Autodesk Fusion 360 part; units mm, degrees
(part 3 of 5)
sketch "Receiving deck roller sketch (8)" plane through (0, -195, 0) normal (0, 1, 0) x (1, 0, 0) in component "MM25 Y carriage and powered receiving deck"
  circle A0 centre (-416, 136) radius 8
extrude "Receiving deck roller (8)" add sketch "Receiving deck roller sketch (8)" along normal blind 390 separate body makes body 155 in component "MM25 Y carriage and powered receiving deck"
ref_plane "WorkPlane17" through (0, -195, 0) normal (0, 1, 0) x (0, 0, 1) in component "MM25 Y carriage and powered receiving deck"
sketch "Receiving deck roller sketch (9)" plane through (0, -195, 0) normal (0, 1, 0) x (1, 0, 0) in component "MM25 Y carriage and powered receiving deck"
  circle A0 centre (-368, 136) radius 8
extrude "Receiving deck roller (9)" add sketch "Receiving deck roller sketch (9)" along normal blind 390 separate body makes body 156 in component "MM25 Y carriage and powered receiving deck"
ref_plane "WorkPlane18" through (0, -195, 0) normal (0, 1, 0) x (0, 0, 1) in component "MM25 Y carriage and powered receiving deck"
sketch "Receiving deck roller sketch (10)" plane through (0, -195, 0) normal (0, 1, 0) x (1, 0, 0) in component "MM25 Y carriage and powered receiving deck"
  circle A0 centre (-320, 136) radius 8
extrude "Receiving deck roller (10)" add sketch "Receiving deck roller sketch (10)" along normal blind 390 separate body makes body 157 in component "MM25 Y carriage and powered receiving deck"
ref_plane "WorkPlane1" through (0, 0, -132) normal (0, 0, 1) x (1, 0, 0) in component "MM26 Folding receiving bridge"
sketch "Thin supported intake bridge sketch" plane through (0, 0, -132) normal (0, 0, 1) x (1, 0, 0) in component "MM26 Folding receiving bridge"
  line L0 (-310, -190) -> (-255, -190)
  line L1 (-255, -190) -> (-255, 190)
  line L2 (-255, 190) -> (-310, 190)
  line L3 (-310, 190) -> (-310, -190)
extrude "Thin supported intake bridge" add sketch "Thin supported intake bridge sketch" along normal blind 4 separate body makes body 158 in component "MM26 Folding receiving bridge"
sketch "Sketch11" plane through (0, 0, 0) normal (0, 0, 1) x (1, 0, 0) in component "MM01 Pressure shell and neck"
sketch "Sketch4" plane through (0, 0, 0) normal (0, 0, 1) x (1, 0, 0) in component "MM24 Elevator Z crossbeam"
sketch "Sketch19" plane through (0, 0, 0) normal (0, 0, 1) x (1, 0, 0) in component "MM25 Y carriage and powered receiving deck"
  point P0 (-310, 0)
ref_plane "WorkPlane1" through (0, 0, -255) normal (0, 0, 1) x (1, 0, 0) in component "MM40 Receiver fixed guide beams"
sketch "Fixed guide box beam sketch" plane through (0, 0, -255) normal (0, 0, 1) x (1, 0, 0) in component "MM40 Receiver fixed guide beams"
  line L0 (-3300, -190) -> (-1660, -190)
  line L1 (-1660, -190) -> (-1660, -160)
  line L2 (-1660, -160) -> (-3300, -160)
  line L3 (-3300, -160) -> (-3300, -190)
extrude "Fixed guide box beam" add sketch "Fixed guide box beam sketch" along normal blind 50 separate body makes body 159 in component "MM40 Receiver fixed guide beams"
ref_plane "WorkPlane2" through (0, 0, -252) normal (0, 0, 1) x (1, 0, 0) in component "MM40 Receiver fixed guide beams"
sketch "Guide beam hollow section sketch" plane through (0, 0, -252) normal (0, 0, 1) x (1, 0, 0) in component "MM40 Receiver fixed guide beams"
  line L0 (-3301, -187) -> (-1659, -187)
  line L1 (-1659, -187) -> (-1659, -163)
  line L2 (-1659, -163) -> (-3301, -163)
  line L3 (-3301, -163) -> (-3301, -187)
extrude "Guide beam hollow section" cut sketch "Guide beam hollow section sketch" along normal blind 44 bodies 159 in component "MM40 Receiver fixed guide beams"
ref_plane "WorkPlane3" through (0, 0, -255) normal (0, 0, 1) x (1, 0, 0) in component "MM40 Receiver fixed guide beams"
sketch "Fixed guide box beam sketch (1)" plane through (0, 0, -255) normal (0, 0, 1) x (1, 0, 0) in component "MM40 Receiver fixed guide beams"
  line L0 (-3300, 160) -> (-1660, 160)
  line L1 (-1660, 160) -> (-1660, 190)
  line L2 (-1660, 190) -> (-3300, 190)
  line L3 (-3300, 190) -> (-3300, 160)
extrude "Fixed guide box beam (1)" add sketch "Fixed guide box beam sketch (1)" along normal blind 50 separate body makes body 160 in component "MM40 Receiver fixed guide beams"
ref_plane "WorkPlane4" through (0, 0, -252) normal (0, 0, 1) x (1, 0, 0) in component "MM40 Receiver fixed guide beams"
sketch "Guide beam hollow section sketch (1)" plane through (0, 0, -252) normal (0, 0, 1) x (1, 0, 0) in component "MM40 Receiver fixed guide beams"
  line L0 (-3301, 163) -> (-1659, 163)
  line L1 (-1659, 163) -> (-1659, 187)
  line L2 (-1659, 187) -> (-3301, 187)
  line L3 (-3301, 187) -> (-3301, 163)
extrude "Guide beam hollow section (1)" cut sketch "Guide beam hollow section sketch (1)" along normal blind 44 bodies 159 160 in component "MM40 Receiver fixed guide beams"
ref_plane "WorkPlane1" through (0, 0, -650) normal (0, 0, 1) x (1, 0, 0) in component "MM41 Receiver mounting stand"
sketch "Bolted mounting foot sketch" plane through (0, 0, -650) normal (0, 0, 1) x (1, 0, 0) in component "MM41 Receiver mounting stand"
  line L0 (-3250, -225) -> (-3150, -225)
  line L1 (-3150, -225) -> (-3150, -125)
  line L2 (-3150, -125) -> (-3250, -125)
  line L3 (-3250, -125) -> (-3250, -225)
extrude "Bolted mounting foot" add sketch "Bolted mounting foot sketch" along normal blind 20 separate body makes body 161 in component "MM41 Receiver mounting stand"
ref_plane "WorkPlane2" through (0, 0, -630) normal (0, 0, 1) x (1, 0, 0) in component "MM41 Receiver mounting stand"
sketch "Vertical support post sketch" plane through (0, 0, -630) normal (0, 0, 1) x (1, 0, 0) in component "MM41 Receiver mounting stand"
  line L0 (-3230, -205) -> (-3170, -205)
  line L1 (-3170, -205) -> (-3170, -145)
  line L2 (-3170, -145) -> (-3230, -145)
  line L3 (-3230, -145) -> (-3230, -205)
extrude "Vertical support post" add sketch "Vertical support post sketch" along normal blind 315 separate body makes body 162 in component "MM41 Receiver mounting stand"
ref_plane "WorkPlane3" through (0, 0, -631) normal (0, 0, 1) x (1, 0, 0) in component "MM41 Receiver mounting stand"
sketch "Post hollow section sketch" plane through (0, 0, -631) normal (0, 0, 1) x (1, 0, 0) in component "MM41 Receiver mounting stand"
  line L0 (-3224, -199) -> (-3176, -199)
  line L1 (-3176, -199) -> (-3176, -151)
  line L2 (-3176, -151) -> (-3224, -151)
  line L3 (-3224, -151) -> (-3224, -199)
extrude "Post hollow section" cut sketch "Post hollow section sketch" along normal blind 377 bodies 161 162 in component "MM41 Receiver mounting stand"
ref_plane "WorkPlane4" through (0, 0, -655) normal (0, 0, 1) x (1, 0, 0) in component "MM41 Receiver mounting stand"
sketch "M8 mounting clearance sketch" plane through (0, 0, -655) normal (0, 0, 1) x (1, 0, 0) in component "MM41 Receiver mounting stand"
  circle A0 centre (-3238, -213) radius 4.25
extrude "M8 mounting clearance" cut sketch "M8 mounting clearance sketch" along normal blind 30 bodies 161 162 in component "MM41 Receiver mounting stand"
ref_plane "WorkPlane5" through (0, 0, -655) normal (0, 0, 1) x (1, 0, 0) in component "MM41 Receiver mounting stand"
sketch "M8 mounting clearance sketch (1)" plane through (0, 0, -655) normal (0, 0, 1) x (1, 0, 0) in component "MM41 Receiver mounting stand"
  circle A0 centre (-3238, -137) radius 4.25
extrude "M8 mounting clearance (1)" cut sketch "M8 mounting clearance sketch (1)" along normal blind 30 bodies 161 162 in component "MM41 Receiver mounting stand"
ref_plane "WorkPlane6" through (0, 0, -655) normal (0, 0, 1) x (1, 0, 0) in component "MM41 Receiver mounting stand"
sketch "M8 mounting clearance sketch (2)" plane through (0, 0, -655) normal (0, 0, 1) x (1, 0, 0) in component "MM41 Receiver mounting stand"
  circle A0 centre (-3162, -213) radius 4.25
extrude "M8 mounting clearance (2)" cut sketch "M8 mounting clearance sketch (2)" along normal blind 30 bodies 161 162 in component "MM41 Receiver mounting stand"
ref_plane "WorkPlane7" through (0, 0, -655) normal (0, 0, 1) x (1, 0, 0) in component "MM41 Receiver mounting stand"
sketch "M8 mounting clearance sketch (3)" plane through (0, 0, -655) normal (0, 0, 1) x (1, 0, 0) in component "MM41 Receiver mounting stand"
  circle A0 centre (-3162, -137) radius 4.25
extrude "M8 mounting clearance (3)" cut sketch "M8 mounting clearance sketch (3)" along normal blind 30 bodies 161 162 in component "MM41 Receiver mounting stand"
ref_plane "WorkPlane8" through (0, 0, -650) normal (0, 0, 1) x (1, 0, 0) in component "MM41 Receiver mounting stand"
sketch "Bolted mounting foot sketch (1)" plane through (0, 0, -650) normal (0, 0, 1) x (1, 0, 0) in component "MM41 Receiver mounting stand"
  line L0 (-3250, 125) -> (-3150, 125)
  line L1 (-3150, 125) -> (-3150, 225)
  line L2 (-3150, 225) -> (-3250, 225)
  line L3 (-3250, 225) -> (-3250, 125)
extrude "Bolted mounting foot (1)" add sketch "Bolted mounting foot sketch (1)" along normal blind 20 separate body makes body 163 in component "MM41 Receiver mounting stand"
ref_plane "WorkPlane9" through (0, 0, -630) normal (0, 0, 1) x (1, 0, 0) in component "MM41 Receiver mounting stand"
sketch "Vertical support post sketch (1)" plane through (0, 0, -630) normal (0, 0, 1) x (1, 0, 0) in component "MM41 Receiver mounting stand"
  line L0 (-3230, 145) -> (-3170, 145)
  line L1 (-3170, 145) -> (-3170, 205)
  line L2 (-3170, 205) -> (-3230, 205)
  line L3 (-3230, 205) -> (-3230, 145)
extrude "Vertical support post (1)" add sketch "Vertical support post sketch (1)" along normal blind 315 separate body makes body 164 in component "MM41 Receiver mounting stand"
ref_plane "WorkPlane10" through (0, 0, -631) normal (0, 0, 1) x (1, 0, 0) in component "MM41 Receiver mounting stand"
sketch "Post hollow section sketch (1)" plane through (0, 0, -631) normal (0, 0, 1) x (1, 0, 0) in component "MM41 Receiver mounting stand"
  line L0 (-3224, 151) -> (-3176, 151)
  line L1 (-3176, 151) -> (-3176, 199)
  line L2 (-3176, 199) -> (-3224, 199)
  line L3 (-3224, 199) -> (-3224, 151)
extrude "Post hollow section (1)" cut sketch "Post hollow section sketch (1)" along normal blind 377 bodies 161 162 163 164 in component "MM41 Receiver mounting stand"
ref_plane "WorkPlane11" through (0, 0, -655) normal (0, 0, 1) x (1, 0, 0) in component "MM41 Receiver mounting stand"
sketch "M8 mounting clearance sketch (4)" plane through (0, 0, -655) normal (0, 0, 1) x (1, 0, 0) in component "MM41 Receiver mounting stand"
  circle A0 centre (-3238, 137) radius 4.25
extrude "M8 mounting clearance (4)" cut sketch "M8 mounting clearance sketch (4)" along normal blind 30 bodies 161 162 163 164 in component "MM41 Receiver mounting stand"
ref_plane "WorkPlane12" through (0, 0, -655) normal (0, 0, 1) x (1, 0, 0) in component "MM41 Receiver mounting stand"
sketch "M8 mounting clearance sketch (5)" plane through (0, 0, -655) normal (0, 0, 1) x (1, 0, 0) in component "MM41 Receiver mounting stand"
  circle A0 centre (-3238, 213) radius 4.25
extrude "M8 mounting clearance (5)" cut sketch "M8 mounting clearance sketch (5)" along normal blind 30 bodies 161 162 163 164 in component "MM41 Receiver mounting stand"
ref_plane "WorkPlane13" through (0, 0, -655) normal (0, 0, 1) x (1, 0, 0) in component "MM41 Receiver mounting stand"
sketch "M8 mounting clearance sketch (6)" plane through (0, 0, -655) normal (0, 0, 1) x (1, 0, 0) in component "MM41 Receiver mounting stand"
  circle A0 centre (-3162, 137) radius 4.25
extrude "M8 mounting clearance (6)" cut sketch "M8 mounting clearance sketch (6)" along normal blind 30 bodies 161 162 163 164 in component "MM41 Receiver mounting stand"
ref_plane "WorkPlane14" through (0, 0, -655) normal (0, 0, 1) x (1, 0, 0) in component "MM41 Receiver mounting stand"
sketch "M8 mounting clearance sketch (7)" plane through (0, 0, -655) normal (0, 0, 1) x (1, 0, 0) in component "MM41 Receiver mounting stand"
  circle A0 centre (-3162, 213) radius 4.25
extrude "M8 mounting clearance (7)" cut sketch "M8 mounting clearance sketch (7)" along normal blind 30 bodies 161 162 163 164 in component "MM41 Receiver mounting stand"
ref_plane "WorkPlane15" through (0, 0, -650) normal (0, 0, 1) x (1, 0, 0) in component "MM41 Receiver mounting stand"
sketch "Bolted mounting foot sketch (2)" plane through (0, 0, -650) normal (0, 0, 1) x (1, 0, 0) in component "MM41 Receiver mounting stand"
  line L0 (-2450, -225) -> (-2350, -225)
  line L1 (-2350, -225) -> (-2350, -125)
  line L2 (-2350, -125) -> (-2450, -125)
  line L3 (-2450, -125) -> (-2450, -225)
extrude "Bolted mounting foot (2)" add sketch "Bolted mounting foot sketch (2)" along normal blind 20 separate body makes body 165 in component "MM41 Receiver mounting stand"
ref_plane "WorkPlane16" through (0, 0, -630) normal (0, 0, 1) x (1, 0, 0) in component "MM41 Receiver mounting stand"
sketch "Vertical support post sketch (2)" plane through (0, 0, -630) normal (0, 0, 1) x (1, 0, 0) in component "MM41 Receiver mounting stand"
  line L0 (-2430, -205) -> (-2370, -205)
  line L1 (-2370, -205) -> (-2370, -145)
  line L2 (-2370, -145) -> (-2430, -145)
  line L3 (-2430, -145) -> (-2430, -205)
extrude "Vertical support post (2)" add sketch "Vertical support post sketch (2)" along normal blind 315 separate body makes body 166 in component "MM41 Receiver mounting stand"
ref_plane "WorkPlane17" through (0, 0, -631) normal (0, 0, 1) x (1, 0, 0) in component "MM41 Receiver mounting stand"
sketch "Post hollow section sketch (2)" plane through (0, 0, -631) normal (0, 0, 1) x (1, 0, 0) in component "MM41 Receiver mounting stand"
  line L0 (-2424, -199) -> (-2376, -199)
  line L1 (-2376, -199) -> (-2376, -151)
  line L2 (-2376, -151) -> (-2424, -151)
  line L3 (-2424, -151) -> (-2424, -199)
extrude "Post hollow section (2)" cut sketch "Post hollow section sketch (2)" along normal blind 377 bodies 161 162 163 164 165 166 in component "MM41 Receiver mounting stand"
ref_plane "WorkPlane18" through (0, 0, -655) normal (0, 0, 1) x (1, 0, 0) in component "MM41 Receiver mounting stand"
sketch "M8 mounting clearance sketch (8)" plane through (0, 0, -655) normal (0, 0, 1) x (1, 0, 0) in component "MM41 Receiver mounting stand"
  circle A0 centre (-2438, -213) radius 4.25
extrude "M8 mounting clearance (8)" cut sketch "M8 mounting clearance sketch (8)" along normal blind 30 bodies 161 162 163 164 165 166 in component "MM41 Receiver mounting stand"
ref_plane "WorkPlane19" through (0, 0, -655) normal (0, 0, 1) x (1, 0, 0) in component "MM41 Receiver mounting stand"
sketch "M8 mounting clearance sketch (9)" plane through (0, 0, -655) normal (0, 0, 1) x (1, 0, 0) in component "MM41 Receiver mounting stand"
  circle A0 centre (-2438, -137) radius 4.25
extrude "M8 mounting clearance (9)" cut sketch "M8 mounting clearance sketch (9)" along normal blind 30 bodies 161 162 163 164 165 166 in component "MM41 Receiver mounting stand"
ref_plane "WorkPlane20" through (0, 0, -655) normal (0, 0, 1) x (1, 0, 0) in component "MM41 Receiver mounting stand"
sketch "M8 mounting clearance sketch (10)" plane through (0, 0, -655) normal (0, 0, 1) x (1, 0, 0) in component "MM41 Receiver mounting stand"
  circle A0 centre (-2362, -213) radius 4.25
extrude "M8 mounting clearance (10)" cut sketch "M8 mounting clearance sketch (10)" along normal blind 30 bodies 161 162 163 164 165 166 in component "MM41 Receiver mounting stand"
ref_plane "WorkPlane21" through (0, 0, -655) normal (0, 0, 1) x (1, 0, 0) in component "MM41 Receiver mounting stand"
sketch "M8 mounting clearance sketch (11)" plane through (0, 0, -655) normal (0, 0, 1) x (1, 0, 0) in component "MM41 Receiver mounting stand"
  circle A0 centre (-2362, -137) radius 4.25
extrude "M8 mounting clearance (11)" cut sketch "M8 mounting clearance sketch (11)" along normal blind 30 bodies 161 162 163 164 165 166 in component "MM41 Receiver mounting stand"
ref_plane "WorkPlane22" through (0, 0, -650) normal (0, 0, 1) x (1, 0, 0) in component "MM41 Receiver mounting stand"
sketch "Bolted mounting foot sketch (3)" plane through (0, 0, -650) normal (0, 0, 1) x (1, 0, 0) in component "MM41 Receiver mounting stand"
  line L0 (-2450, 125) -> (-2350, 125)
  line L1 (-2350, 125) -> (-2350, 225)
  line L2 (-2350, 225) -> (-2450, 225)
  line L3 (-2450, 225) -> (-2450, 125)
extrude "Bolted mounting foot (3)" add sketch "Bolted mounting foot sketch (3)" along normal blind 20 separate body makes body 167 in component "MM41 Receiver mounting stand"
ref_plane "WorkPlane23" through (0, 0, -630) normal (0, 0, 1) x (1, 0, 0) in component "MM41 Receiver mounting stand"
sketch "Vertical support post sketch (3)" plane through (0, 0, -630) normal (0, 0, 1) x (1, 0, 0) in component "MM41 Receiver mounting stand"
  line L0 (-2430, 145) -> (-2370, 145)
  line L1 (-2370, 145) -> (-2370, 205)
  line L2 (-2370, 205) -> (-2430, 205)
  line L3 (-2430, 205) -> (-2430, 145)
extrude "Vertical support post (3)" add sketch "Vertical support post sketch (3)" along normal blind 315 separate body makes body 168 in component "MM41 Receiver mounting stand"
ref_plane "WorkPlane24" through (0, 0, -631) normal (0, 0, 1) x (1, 0, 0) in component "MM41 Receiver mounting stand"
sketch "Post hollow section sketch (3)" plane through (0, 0, -631) normal (0, 0, 1) x (1, 0, 0) in component "MM41 Receiver mounting stand"
  line L0 (-2424, 151) -> (-2376, 151)
  line L1 (-2376, 151) -> (-2376, 199)
  line L2 (-2376, 199) -> (-2424, 199)
  line L3 (-2424, 199) -> (-2424, 151)
extrude "Post hollow section (3)" cut sketch "Post hollow section sketch (3)" along normal blind 377 bodies 161 162 163 164 165 166 167 168 in component "MM41 Receiver mounting stand"
ref_plane "WorkPlane25" through (0, 0, -655) normal (0, 0, 1) x (1, 0, 0) in component "MM41 Receiver mounting stand"
sketch "M8 mounting clearance sketch (12)" plane through (0, 0, -655) normal (0, 0, 1) x (1, 0, 0) in component "MM41 Receiver mounting stand"
  circle A0 centre (-2438, 137) radius 4.25
extrude "M8 mounting clearance (12)" cut sketch "M8 mounting clearance sketch (12)" along normal blind 30 bodies 161 162 163 164 165 166 167 168 in component "MM41 Receiver mounting stand"
ref_plane "WorkPlane26" through (0, 0, -655) normal (0, 0, 1) x (1, 0, 0) in component "MM41 Receiver mounting stand"
sketch "M8 mounting clearance sketch (13)" plane through (0, 0, -655) normal (0, 0, 1) x (1, 0, 0) in component "MM41 Receiver mounting stand"
  circle A0 centre (-2438, 213) radius 4.25
extrude "M8 mounting clearance (13)" cut sketch "M8 mounting clearance sketch (13)" along normal blind 30 bodies 161 162 163 164 165 166 167 168 in component "MM41 Receiver mounting stand"
ref_plane "WorkPlane27" through (0, 0, -655) normal (0, 0, 1) x (1, 0, 0) in component "MM41 Receiver mounting stand"
sketch "M8 mounting clearance sketch (14)" plane through (0, 0, -655) normal (0, 0, 1) x (1, 0, 0) in component "MM41 Receiver mounting stand"
  circle A0 centre (-2362, 137) radius 4.25
extrude "M8 mounting clearance (14)" cut sketch "M8 mounting clearance sketch (14)" along normal blind 30 bodies 161 162 163 164 165 166 167 168 in component "MM41 Receiver mounting stand"
ref_plane "WorkPlane28" through (0, 0, -655) normal (0, 0, 1) x (1, 0, 0) in component "MM41 Receiver mounting stand"
sketch "M8 mounting clearance sketch (15)" plane through (0, 0, -655) normal (0, 0, 1) x (1, 0, 0) in component "MM41 Receiver mounting stand"
  circle A0 centre (-2362, 213) radius 4.25
extrude "M8 mounting clearance (15)" cut sketch "M8 mounting clearance sketch (15)" along normal blind 30 bodies 161 162 163 164 165 166 167 168 in component "MM41 Receiver mounting stand"
ref_plane "WorkPlane1" through (0, 0, -680) normal (0, 0, 1) x (1, 0, 0) in component "REF Existing receiver structural deck ASSUMED"
sketch "Assumed receiver structural deck sketch" plane through (0, 0, -680) normal (0, 0, 1) x (1, 0, 0) in component "REF Existing receiver structural deck ASSUMED"
  line L0 (-3400, -475) -> (-2300, -475)
  line L1 (-2300, -475) -> (-2300, 475)
  line L2 (-2300, 475) -> (-3400, 475)
  line L3 (-3400, 475) -> (-3400, -475)
extrude "Assumed receiver structural deck" add sketch "Assumed receiver structural deck sketch" along normal blind 30 separate body makes body 169 in component "REF Existing receiver structural deck ASSUMED"
ref_plane "WorkPlane2" through (0, 0, -685) normal (0, 0, 1) x (1, 0, 0) in component "REF Existing receiver structural deck ASSUMED"
sketch "Reference deck bolt clearance sketch" plane through (0, 0, -685) normal (0, 0, 1) x (1, 0, 0) in component "REF Existing receiver structural deck ASSUMED"
  circle A0 centre (-3238, -213) radius 4.25
extrude "Reference deck bolt clearance" cut sketch "Reference deck bolt clearance sketch" along normal blind 40 bodies 169 in component "REF Existing receiver structural deck ASSUMED"
ref_plane "WorkPlane3" through (0, 0, -685) normal (0, 0, 1) x (1, 0, 0) in component "REF Existing receiver structural deck ASSUMED"
sketch "Reference deck bolt clearance sketch (1)" plane through (0, 0, -685) normal (0, 0, 1) x (1, 0, 0) in component "REF Existing receiver structural deck ASSUMED"
  circle A0 centre (-3238, -137) radius 4.25
extrude "Reference deck bolt clearance (1)" cut sketch "Reference deck bolt clearance sketch (1)" along normal blind 40 bodies 169 in component "REF Existing receiver structural deck ASSUMED"
ref_plane "WorkPlane4" through (0, 0, -685) normal (0, 0, 1) x (1, 0, 0) in component "REF Existing receiver structural deck ASSUMED"
sketch "Reference deck bolt clearance sketch (2)" plane through (0, 0, -685) normal (0, 0, 1) x (1, 0, 0) in component "REF Existing receiver structural deck ASSUMED"
  circle A0 centre (-3162, -213) radius 4.25
extrude "Reference deck bolt clearance (2)" cut sketch "Reference deck bolt clearance sketch (2)" along normal blind 40 bodies 169 in component "REF Existing receiver structural deck ASSUMED"
ref_plane "WorkPlane5" through (0, 0, -685) normal (0, 0, 1) x (1, 0, 0) in component "REF Existing receiver structural deck ASSUMED"
sketch "Reference deck bolt clearance sketch (3)" plane through (0, 0, -685) normal (0, 0, 1) x (1, 0, 0) in component "REF Existing receiver structural deck ASSUMED"
  circle A0 centre (-3162, -137) radius 4.25
extrude "Reference deck bolt clearance (3)" cut sketch "Reference deck bolt clearance sketch (3)" along normal blind 40 bodies 169 in component "REF Existing receiver structural deck ASSUMED"
ref_plane "WorkPlane6" through (0, 0, -685) normal (0, 0, 1) x (1, 0, 0) in component "REF Existing receiver structural deck ASSUMED"
sketch "Reference deck bolt clearance sketch (4)" plane through (0, 0, -685) normal (0, 0, 1) x (1, 0, 0) in component "REF Existing receiver structural deck ASSUMED"
  circle A0 centre (-3238, 137) radius 4.25
extrude "Reference deck bolt clearance (4)" cut sketch "Reference deck bolt clearance sketch (4)" along normal blind 40 bodies 169 in component "REF Existing receiver structural deck ASSUMED"
ref_plane "WorkPlane7" through (0, 0, -685) normal (0, 0, 1) x (1, 0, 0) in component "REF Existing receiver structural deck ASSUMED"
sketch "Reference deck bolt clearance sketch (5)" plane through (0, 0, -685) normal (0, 0, 1) x (1, 0, 0) in component "REF Existing receiver structural deck ASSUMED"
  circle A0 centre (-3238, 213) radius 4.25
extrude "Reference deck bolt clearance (5)" cut sketch "Reference deck bolt clearance sketch (5)" along normal blind 40 bodies 169 in component "REF Existing receiver structural deck ASSUMED"
ref_plane "WorkPlane8" through (0, 0, -685) normal (0, 0, 1) x (1, 0, 0) in component "REF Existing receiver structural deck ASSUMED"
sketch "Reference deck bolt clearance sketch (6)" plane through (0, 0, -685) normal (0, 0, 1) x (1, 0, 0) in component "REF Existing receiver structural deck ASSUMED"
  circle A0 centre (-3162, 137) radius 4.25
extrude "Reference deck bolt clearance (6)" cut sketch "Reference deck bolt clearance sketch (6)" along normal blind 40 bodies 169 in component "REF Existing receiver structural deck ASSUMED"
ref_plane "WorkPlane9" through (0, 0, -685) normal (0, 0, 1) x (1, 0, 0) in component "REF Existing receiver structural deck ASSUMED"
sketch "Reference deck bolt clearance sketch (7)" plane through (0, 0, -685) normal (0, 0, 1) x (1, 0, 0) in component "REF Existing receiver structural deck ASSUMED"
  circle A0 centre (-3162, 213) radius 4.25
extrude "Reference deck bolt clearance (7)" cut sketch "Reference deck bolt clearance sketch (7)" along normal blind 40 bodies 169 in component "REF Existing receiver structural deck ASSUMED"
ref_plane "WorkPlane10" through (0, 0, -685) normal (0, 0, 1) x (1, 0, 0) in component "REF Existing receiver structural deck ASSUMED"
sketch "Reference deck bolt clearance sketch (8)" plane through (0, 0, -685) normal (0, 0, 1) x (1, 0, 0) in component "REF Existing receiver structural deck ASSUMED"
  circle A0 centre (-2438, -213) radius 4.25
extrude "Reference deck bolt clearance (8)" cut sketch "Reference deck bolt clearance sketch (8)" along normal blind 40 bodies 169 in component "REF Existing receiver structural deck ASSUMED"
ref_plane "WorkPlane11" through (0, 0, -685) normal (0, 0, 1) x (1, 0, 0) in component "REF Existing receiver structural deck ASSUMED"
sketch "Reference deck bolt clearance sketch (9)" plane through (0, 0, -685) normal (0, 0, 1) x (1, 0, 0) in component "REF Existing receiver structural deck ASSUMED"
  circle A0 centre (-2438, -137) radius 4.25
extrude "Reference deck bolt clearance (9)" cut sketch "Reference deck bolt clearance sketch (9)" along normal blind 40 bodies 169 in component "REF Existing receiver structural deck ASSUMED"
ref_plane "WorkPlane12" through (0, 0, -685) normal (0, 0, 1) x (1, 0, 0) in component "REF Existing receiver structural deck ASSUMED"
sketch "Reference deck bolt clearance sketch (10)" plane through (0, 0, -685) normal (0, 0, 1) x (1, 0, 0) in component "REF Existing receiver structural deck ASSUMED"
  circle A0 centre (-2362, -213) radius 4.25
extrude "Reference deck bolt clearance (10)" cut sketch "Reference deck bolt clearance sketch (10)" along normal blind 40 bodies 169 in component "REF Existing receiver structural deck ASSUMED"
ref_plane "WorkPlane13" through (0, 0, -685) normal (0, 0, 1) x (1, 0, 0) in component "REF Existing receiver structural deck ASSUMED"
sketch "Reference deck bolt clearance sketch (11)" plane through (0, 0, -685) normal (0, 0, 1) x (1, 0, 0) in component "REF Existing receiver structural deck ASSUMED"
  circle A0 centre (-2362, -137) radius 4.25
extrude "Reference deck bolt clearance (11)" cut sketch "Reference deck bolt clearance sketch (11)" along normal blind 40 bodies 169 in component "REF Existing receiver structural deck ASSUMED"
ref_plane "WorkPlane14" through (0, 0, -685) normal (0, 0, 1) x (1, 0, 0) in component "REF Existing receiver structural deck ASSUMED"
sketch "Reference deck bolt clearance sketch (12)" plane through (0, 0, -685) normal (0, 0, 1) x (1, 0, 0) in component "REF Existing receiver structural deck ASSUMED"
  circle A0 centre (-2438, 137) radius 4.25
extrude "Reference deck bolt clearance (12)" cut sketch "Reference deck bolt clearance sketch (12)" along normal blind 40 bodies 169 in component "REF Existing receiver structural deck ASSUMED"
ref_plane "WorkPlane15" through (0, 0, -685) normal (0, 0, 1) x (1, 0, 0) in component "REF Existing receiver structural deck ASSUMED"
sketch "Reference deck bolt clearance sketch (13)" plane through (0, 0, -685) normal (0, 0, 1) x (1, 0, 0) in component "REF Existing receiver structural deck ASSUMED"
  circle A0 centre (-2438, 213) radius 4.25
extrude "Reference deck bolt clearance (13)" cut sketch "Reference deck bolt clearance sketch (13)" along normal blind 40 bodies 169 in component "REF Existing receiver structural deck ASSUMED"
ref_plane "WorkPlane16" through (0, 0, -685) normal (0, 0, 1) x (1, 0, 0) in component "REF Existing receiver structural deck ASSUMED"
sketch "Reference deck bolt clearance sketch (14)" plane through (0, 0, -685) normal (0, 0, 1) x (1, 0, 0) in component "REF Existing receiver structural deck ASSUMED"
  circle A0 centre (-2362, 137) radius 4.25
extrude "Reference deck bolt clearance (14)" cut sketch "Reference deck bolt clearance sketch (14)" along normal blind 40 bodies 169 in component "REF Existing receiver structural deck ASSUMED"
ref_plane "WorkPlane17" through (0, 0, -685) normal (0, 0, 1) x (1, 0, 0) in component "REF Existing receiver structural deck ASSUMED"
sketch "Reference deck bolt clearance sketch (15)" plane through (0, 0, -685) normal (0, 0, 1) x (1, 0, 0) in component "REF Existing receiver structural deck ASSUMED"
  circle A0 centre (-2362, 213) radius 4.25
extrude "Reference deck bolt clearance (15)" cut sketch "Reference deck bolt clearance sketch (15)" along normal blind 40 bodies 169 in component "REF Existing receiver structural deck ASSUMED"
ref_plane "WorkPlane1" through (0, 0, -50) normal (0, 0, 1) x (1, 0, 0) in component "MM42 Captured receiver guide carriage"
sketch "Captured bearing housing sketch" plane through (0, 0, -50) normal (0, 0, 1) x (1, 0, 0) in component "MM42 Captured receiver guide carriage"
  line L0 (-40, -27) -> (40, -27)
  line L1 (40, -27) -> (40, 27)
  line L2 (40, 27) -> (-40, 27)
  line L3 (-40, 27) -> (-40, -27)
extrude "Captured bearing housing" add sketch "Captured bearing housing sketch" along normal blind 100 separate body makes body 170 in component "MM42 Captured receiver guide carriage"
ref_plane "WorkPlane2" through (0, 0, -26) normal (0, 0, 1) x (1, 0, 0) in component "MM42 Captured receiver guide carriage"
sketch "Guide running clearance sketch" plane through (0, 0, -26) normal (0, 0, 1) x (1, 0, 0) in component "MM42 Captured receiver guide carriage"
  line L0 (-42, -16) -> (42, -16)
  line L1 (42, -16) -> (42, 16)
  line L2 (42, 16) -> (-42, 16)
  line L3 (-42, 16) -> (-42, -16)
extrude "Guide running clearance" cut sketch "Guide running clearance sketch" along normal blind 52 bodies 170 in component "MM42 Captured receiver guide carriage"
ref_plane "WorkPlane3" through (0, 0, -26) normal (0, 0, 1) x (1, 0, 0) in component "MM42 Captured receiver guide carriage"
sketch "Bearing contact liner sketch" plane through (0, 0, -26) normal (0, 0, 1) x (1, 0, 0) in component "MM42 Captured receiver guide carriage"
  line L0 (-30, -14) -> (30, -14)
  line L1 (30, -14) -> (30, 14)
  line L2 (30, 14) -> (-30, 14)
  line L3 (-30, 14) -> (-30, -14)
extrude "Bearing contact liner" add sketch "Bearing contact liner sketch" along normal blind 1 separate body makes body 171 in component "MM42 Captured receiver guide carriage"
ref_plane "WorkPlane4" through (0, 0, 25) normal (0, 0, 1) x (1, 0, 0) in component "MM42 Captured receiver guide carriage"
sketch "Bearing contact liner sketch (1)" plane through (0, 0, 25) normal (0, 0, 1) x (1, 0, 0) in component "MM42 Captured receiver guide carriage"
  line L0 (-30, -14) -> (30, -14)
  line L1 (30, -14) -> (30, 14)
  line L2 (30, 14) -> (-30, 14)
  line L3 (-30, 14) -> (-30, -14)
extrude "Bearing contact liner (1)" add sketch "Bearing contact liner sketch (1)" along normal blind 1 separate body makes body 172 in component "MM42 Captured receiver guide carriage"
ref_plane "WorkPlane5" through (0, 0, -20) normal (0, 0, 1) x (1, 0, 0) in component "MM42 Captured receiver guide carriage"
sketch "Lateral contact liner sketch" plane through (0, 0, -20) normal (0, 0, 1) x (1, 0, 0) in component "MM42 Captured receiver guide carriage"
  line L0 (-30, -16) -> (30, -16)
  line L1 (30, -16) -> (30, -15)
  line L2 (30, -15) -> (-30, -15)
  line L3 (-30, -15) -> (-30, -16)
extrude "Lateral contact liner" add sketch "Lateral contact liner sketch" along normal blind 40 separate body makes body 173 in component "MM42 Captured receiver guide carriage"
ref_plane "WorkPlane6" through (0, 0, -20) normal (0, 0, 1) x (1, 0, 0) in component "MM42 Captured receiver guide carriage"
sketch "Lateral contact liner sketch (1)" plane through (0, 0, -20) normal (0, 0, 1) x (1, 0, 0) in component "MM42 Captured receiver guide carriage"
  line L0 (-30, 15) -> (30, 15)
  line L1 (30, 15) -> (30, 16)
  line L2 (30, 16) -> (-30, 16)
  line L3 (-30, 16) -> (-30, 15)
extrude "Lateral contact liner (1)" add sketch "Lateral contact liner sketch (1)" along normal blind 40 separate body makes body 174 in component "MM42 Captured receiver guide carriage"
ref_plane "WorkPlane1" through (0, 0, -685) normal (0, 0, 1) x (1, 0, 0) in component "MM43 Receiver M8 mounting fastener set"
sketch "M8 through bolt sketch" plane through (0, 0, -685) normal (0, 0, 1) x (1, 0, 0) in component "MM43 Receiver M8 mounting fastener set"
  circle A0 centre (0, 0) radius 4
extrude "M8 through bolt" add sketch "M8 through bolt sketch" along normal blind 55 separate body makes body 175 in component "MM43 Receiver M8 mounting fastener set"
ref_plane "WorkPlane2" through (0, 0, -630) normal (0, 0, 1) x (1, 0, 0) in component "MM43 Receiver M8 mounting fastener set"
sketch "Bolt head sketch" plane through (0, 0, -630) normal (0, 0, 1) x (1, 0, 0) in component "MM43 Receiver M8 mounting fastener set"
  circle A0 centre (0, 0) radius 7
extrude "Bolt head" add sketch "Bolt head sketch" along normal blind 5 bodies 175 in component "MM43 Receiver M8 mounting fastener set"
ref_plane "WorkPlane3" through (0, 0, -692) normal (0, 0, 1) x (1, 0, 0) in component "MM43 Receiver M8 mounting fastener set"
sketch "Retaining nut envelope sketch" plane through (0, 0, -692) normal (0, 0, 1) x (1, 0, 0) in component "MM43 Receiver M8 mounting fastener set"
  circle A0 centre (0, 0) radius 7
  circle A1 centre (0, 0) radius 4.25
extrude "Retaining nut envelope" add sketch "Retaining nut envelope sketch" along normal blind 12 separate body makes body 176 in component "MM43 Receiver M8 mounting fastener set"
sketch "Sketch5" plane through (0, 0, 0) normal (0, 0, 1) x (1, 0, 0) in component "MM40 Receiver fixed guide beams"
ref_plane "WorkPlane1" through (0, 0, -280) normal (0, 0, 1) x (1, 0, 0) in component "MM44 Receiver screw drive and end supports"
sketch "Fixed motor and reducer envelope sketch" plane through (0, 0, -280) normal (0, 0, 1) x (1, 0, 0) in component "MM44 Receiver screw drive and end supports"
  line L0 (-3360, -50) -> (-3280, -50)
  line L1 (-3280, -50) -> (-3280, 50)
  line L2 (-3280, 50) -> (-3360, 50)
  line L3 (-3360, 50) -> (-3360, -50)
extrude "Fixed motor and reducer envelope" add sketch "Fixed motor and reducer envelope sketch" along normal blind 100 separate body makes body 177 in component "MM44 Receiver screw drive and end supports"
ref_plane "WorkPlane2" through (-3300, 0, 0) normal (1, 0, 0) x (0, 1, 0) in component "MM44 Receiver screw drive and end supports"
sketch "Nominal 16 mm lead screw envelope sketch" plane through (-3300, 0, 0) normal (1, 0, 0) x (0, 0, -1) in component "MM44 Receiver screw drive and end supports"
  circle A0 centre (230, 0) radius 8
extrude "Nominal 16 mm lead screw envelope" add sketch "Nominal 16 mm lead screw envelope sketch" along normal blind 1630 separate body makes body 178 in component "MM44 Receiver screw drive and end supports"
ref_plane "WorkPlane3" through (0, 0, -285) normal (0, 0, 1) x (1, 0, 0) in component "MM44 Receiver screw drive and end supports"
sketch "Guide-mounted end support crossmember sketch" plane through (0, 0, -285) normal (0, 0, 1) x (1, 0, 0) in component "MM44 Receiver screw drive and end supports"
  line L0 (-3300, -190) -> (-3280, -190)
  line L1 (-3280, -190) -> (-3280, 190)
  line L2 (-3280, 190) -> (-3300, 190)
  line L3 (-3300, 190) -> (-3300, -190)
extrude "Guide-mounted end support crossmember" add sketch "Guide-mounted end support crossmember sketch" along normal blind 30 separate body makes body 179 in component "MM44 Receiver screw drive and end supports"
ref_plane "WorkPlane4" through (0, 0, -255) normal (0, 0, 1) x (1, 0, 0) in component "MM44 Receiver screw drive and end supports"
sketch "Screw end-bearing housing envelope sketch" plane through (0, 0, -255) normal (0, 0, 1) x (1, 0, 0) in component "MM44 Receiver screw drive and end supports"
  line L0 (-3300, -30) -> (-3280, -30)
  line L1 (-3280, -30) -> (-3280, 30)
  line L2 (-3280, 30) -> (-3300, 30)
  line L3 (-3300, 30) -> (-3300, -30)
extrude "Screw end-bearing housing envelope" add sketch "Screw end-bearing housing envelope sketch" along normal blind 50 separate body makes body 180 in component "MM44 Receiver screw drive and end supports"
ref_plane "WorkPlane5" through (0, 0, -285) normal (0, 0, 1) x (1, 0, 0) in component "MM44 Receiver screw drive and end supports"
sketch "Guide-mounted end support crossmember sketch (1)" plane through (0, 0, -285) normal (0, 0, 1) x (1, 0, 0) in component "MM44 Receiver screw drive and end supports"
  line L0 (-1680, -190) -> (-1660, -190)
  line L1 (-1660, -190) -> (-1660, 190)
  line L2 (-1660, 190) -> (-1680, 190)
  line L3 (-1680, 190) -> (-1680, -190)
extrude "Guide-mounted end support crossmember (1)" add sketch "Guide-mounted end support crossmember sketch (1)" along normal blind 30 separate body makes body 181 in component "MM44 Receiver screw drive and end supports"
ref_plane "WorkPlane6" through (0, 0, -255) normal (0, 0, 1) x (1, 0, 0) in component "MM44 Receiver screw drive and end supports"
sketch "Screw end-bearing housing envelope sketch (1)" plane through (0, 0, -255) normal (0, 0, 1) x (1, 0, 0) in component "MM44 Receiver screw drive and end supports"
  line L0 (-1680, -30) -> (-1660, -30)
  line L1 (-1660, -30) -> (-1660, 30)
  line L2 (-1660, 30) -> (-1680, 30)
  line L3 (-1680, 30) -> (-1680, -30)
extrude "Screw end-bearing housing envelope (1)" add sketch "Screw end-bearing housing envelope sketch (1)" along normal blind 50 separate body makes body 182 in component "MM44 Receiver screw drive and end supports"
ref_plane "WorkPlane1" through (0, 0, -255) normal (0, 0, 1) x (1, 0, 0) in component "MM45 Receiver travelling drive nut and yoke"
sketch "Travelling nut housing sketch" plane through (0, 0, -255) normal (0, 0, 1) x (1, 0, 0) in component "MM45 Receiver travelling drive nut and yoke"
  line L0 (-2080, -25) -> (-2020, -25)
  line L1 (-2020, -25) -> (-2020, 25)
  line L2 (-2020, 25) -> (-2080, 25)
  line L3 (-2080, 25) -> (-2080, -25)
extrude "Travelling nut housing" add sketch "Travelling nut housing sketch" along normal blind 50 separate body makes body 183 in component "MM45 Receiver travelling drive nut and yoke"
ref_plane "WorkPlane2" through (-2085, 0, 0) normal (1, 0, 0) x (0, 1, 0) in component "MM45 Receiver travelling drive nut and yoke"
sketch "Screw clearance envelope sketch" plane through (-2085, 0, 0) normal (1, 0, 0) x (0, 0, -1) in component "MM45 Receiver travelling drive nut and yoke"
  circle A0 centre (230, 0) radius 8.25
extrude "Screw clearance envelope" cut sketch "Screw clearance envelope sketch" along normal blind 70 bodies 183 in component "MM45 Receiver travelling drive nut and yoke"
ref_plane "WorkPlane3" through (0, 0, -205) normal (0, 0, 1) x (1, 0, 0) in component "MM45 Receiver travelling drive nut and yoke"
sketch "Conveyor-to-nut support yoke sketch" plane through (0, 0, -205) normal (0, 0, 1) x (1, 0, 0) in component "MM45 Receiver travelling drive nut and yoke"
  line L0 (-2062, -20) -> (-2038, -20)
  line L1 (-2038, -20) -> (-2038, 20)
  line L2 (-2038, 20) -> (-2062, 20)
  line L3 (-2062, 20) -> (-2062, -20)
extrude "Conveyor-to-nut support yoke" add sketch "Conveyor-to-nut support yoke sketch" along normal blind 30 separate body makes body 184 in component "MM45 Receiver travelling drive nut and yoke"
ref_plane "WorkPlane29" through (0, 0, -323) normal (0, 0, 1) x (1, 0, 0) in component "MM41 Receiver mounting stand"
sketch "Post top closure plate sketch" plane through (0, 0, -323) normal (0, 0, 1) x (1, 0, 0) in component "MM41 Receiver mounting stand"
  line L0 (-3224, -199) -> (-3176, -199)
  line L1 (-3176, -199) -> (-3176, -151)
  line L2 (-3176, -151) -> (-3224, -151)
  line L3 (-3224, -151) -> (-3224, -199)
extrude "Post top closure plate" add sketch "Post top closure plate sketch" along normal blind 8 separate body makes body 185 in component "MM41 Receiver mounting stand"
ref_plane "WorkPlane30" through (0, 0, -315) normal (0, 0, 1) x (1, 0, 0) in component "MM41 Receiver mounting stand"
sketch "Narrow guide support neck sketch" plane through (0, 0, -315) normal (0, 0, 1) x (1, 0, 0) in component "MM41 Receiver mounting stand"
  line L0 (-3220, -182) -> (-3180, -182)
  line L1 (-3180, -182) -> (-3180, -168)
  line L2 (-3180, -168) -> (-3220, -168)
  line L3 (-3220, -168) -> (-3220, -182)
extrude "Narrow guide support neck" add sketch "Narrow guide support neck sketch" along normal blind 60 separate body makes body 186 in component "MM41 Receiver mounting stand"
ref_plane "WorkPlane31" through (0, 0, -323) normal (0, 0, 1) x (1, 0, 0) in component "MM41 Receiver mounting stand"
sketch "Post top closure plate sketch (1)" plane through (0, 0, -323) normal (0, 0, 1) x (1, 0, 0) in component "MM41 Receiver mounting stand"
  line L0 (-3224, 151) -> (-3176, 151)
  line L1 (-3176, 151) -> (-3176, 199)
  line L2 (-3176, 199) -> (-3224, 199)
  line L3 (-3224, 199) -> (-3224, 151)
extrude "Post top closure plate (1)" add sketch "Post top closure plate sketch (1)" along normal blind 8 separate body makes body 187 in component "MM41 Receiver mounting stand"
ref_plane "WorkPlane32" through (0, 0, -315) normal (0, 0, 1) x (1, 0, 0) in component "MM41 Receiver mounting stand"
sketch "Narrow guide support neck sketch (1)" plane through (0, 0, -315) normal (0, 0, 1) x (1, 0, 0) in component "MM41 Receiver mounting stand"
  line L0 (-3220, 168) -> (-3180, 168)
  line L1 (-3180, 168) -> (-3180, 182)
  line L2 (-3180, 182) -> (-3220, 182)
  line L3 (-3220, 182) -> (-3220, 168)
extrude "Narrow guide support neck (1)" add sketch "Narrow guide support neck sketch (1)" along normal blind 60 separate body makes body 188 in component "MM41 Receiver mounting stand"
ref_plane "WorkPlane33" through (0, 0, -323) normal (0, 0, 1) x (1, 0, 0) in component "MM41 Receiver mounting stand"
sketch "Post top closure plate sketch (2)" plane through (0, 0, -323) normal (0, 0, 1) x (1, 0, 0) in component "MM41 Receiver mounting stand"
  line L0 (-2424, -199) -> (-2376, -199)
  line L1 (-2376, -199) -> (-2376, -151)
  line L2 (-2376, -151) -> (-2424, -151)
  line L3 (-2424, -151) -> (-2424, -199)
extrude "Post top closure plate (2)" add sketch "Post top closure plate sketch (2)" along normal blind 8 separate body makes body 189 in component "MM41 Receiver mounting stand"
ref_plane "WorkPlane34" through (0, 0, -315) normal (0, 0, 1) x (1, 0, 0) in component "MM41 Receiver mounting stand"
sketch "Narrow guide support neck sketch (2)" plane through (0, 0, -315) normal (0, 0, 1) x (1, 0, 0) in component "MM41 Receiver mounting stand"
  line L0 (-2420, -182) -> (-2380, -182)
  line L1 (-2380, -182) -> (-2380, -168)
  line L2 (-2380, -168) -> (-2420, -168)
  line L3 (-2420, -168) -> (-2420, -182)
extrude "Narrow guide support neck (2)" add sketch "Narrow guide support neck sketch (2)" along normal blind 60 separate body makes body 190 in component "MM41 Receiver mounting stand"
ref_plane "WorkPlane35" through (0, 0, -323) normal (0, 0, 1) x (1, 0, 0) in component "MM41 Receiver mounting stand"
sketch "Post top closure plate sketch (3)" plane through (0, 0, -323) normal (0, 0, 1) x (1, 0, 0) in component "MM41 Receiver mounting stand"
  line L0 (-2424, 151) -> (-2376, 151)
  line L1 (-2376, 151) -> (-2376, 199)
  line L2 (-2376, 199) -> (-2424, 199)
  line L3 (-2424, 199) -> (-2424, 151)
extrude "Post top closure plate (3)" add sketch "Post top closure plate sketch (3)" along normal blind 8 separate body makes body 191 in component "MM41 Receiver mounting stand"
ref_plane "WorkPlane36" through (0, 0, -315) normal (0, 0, 1) x (1, 0, 0) in component "MM41 Receiver mounting stand"
sketch "Narrow guide support neck sketch (3)" plane through (0, 0, -315) normal (0, 0, 1) x (1, 0, 0) in component "MM41 Receiver mounting stand"
  line L0 (-2420, 168) -> (-2380, 168)
  line L1 (-2380, 168) -> (-2380, 182)
  line L2 (-2380, 182) -> (-2420, 182)
  line L3 (-2420, 182) -> (-2420, 168)
extrude "Narrow guide support neck (3)" add sketch "Narrow guide support neck sketch (3)" along normal blind 60 separate body makes body 192 in component "MM41 Receiver mounting stand"
ref_plane "WorkPlane7" through (0, 0, -51) normal (0, 0, 1) x (1, 0, 0) in component "MM42 Captured receiver guide carriage"
sketch "Support-neck running slot sketch" plane through (0, 0, -51) normal (0, 0, 1) x (1, 0, 0) in component "MM42 Captured receiver guide carriage"
  line L0 (-42, -8) -> (42, -8)
  line L1 (42, -8) -> (42, 8)
  line L2 (42, 8) -> (-42, 8)
  line L3 (-42, 8) -> (-42, -8)
extrude "Support-neck running slot" cut sketch "Support-neck running slot sketch" along normal blind 28 bodies 170 171 172 173 174 makes body 193 at (-10, -12, -26) in component "MM42 Captured receiver guide carriage"
ref_plane "WorkPlane3" through (0, 0, -550) normal (0, 0, 1) x (1, 0, 0) in component "MM07 MLI blanket envelope"
sketch "Sunshade bracket blanket clearance sketch" plane through (0, 0, -550) normal (0, 0, 1) x (1, 0, 0) in component "MM07 MLI blanket envelope"
  line L0 (-677, 750) -> (-623, 750)
  line L1 (-623, 750) -> (-623, 990)
  line L2 (-623, 990) -> (-677, 990)
  line L3 (-677, 990) -> (-677, 750)
ref_plane "WorkPlane4" through (0, 0, 430) normal (0, 0, 1) x (1, 0, 0) in component "MM07 MLI blanket envelope"
sketch "Sunshade bracket blanket clearance sketch (1)" plane through (0, 0, 430) normal (0, 0, 1) x (1, 0, 0) in component "MM07 MLI blanket envelope"
  line L0 (-677, 750) -> (-623, 750)
  line L1 (-623, 750) -> (-623, 990)
  line L2 (-623, 990) -> (-677, 990)
  line L3 (-677, 990) -> (-677, 750)
ref_plane "WorkPlane5" through (0, 0, -550) normal (0, 0, 1) x (1, 0, 0) in component "MM07 MLI blanket envelope"
sketch "Sunshade bracket blanket clearance sketch (2)" plane through (0, 0, -550) normal (0, 0, 1) x (1, 0, 0) in component "MM07 MLI blanket envelope"
  line L0 (623, 750) -> (677, 750)
  line L1 (677, 750) -> (677, 990)
  line L2 (677, 990) -> (623, 990)
  line L3 (623, 990) -> (623, 750)
ref_plane "WorkPlane6" through (0, 0, 430) normal (0, 0, 1) x (1, 0, 0) in component "MM07 MLI blanket envelope"
sketch "Sunshade bracket blanket clearance sketch (3)" plane through (0, 0, 430) normal (0, 0, 1) x (1, 0, 0) in component "MM07 MLI blanket envelope"
  line L0 (623, 750) -> (677, 750)
  line L1 (677, 750) -> (677, 990)
  line L2 (677, 990) -> (623, 990)
  line L3 (623, 990) -> (623, 750)
ref_plane "WorkPlane1" through (0, 0, 1018) normal (0, 0, 1) x (1, 0, 0) in component "MM16 Upward-facing radiator panel"
sketch "One point two square metre radiator face sketch" plane through (0, 0, 1018) normal (0, 0, 1) x (1, 0, 0) in component "MM16 Upward-facing radiator panel"
  line L0 (-750, -400) -> (750, -400)
  line L1 (750, -400) -> (750, 400)
  line L2 (750, 400) -> (-750, 400)
  line L3 (-750, 400) -> (-750, -400)
extrude "One point two square metre radiator face" add sketch "One point two square metre radiator face sketch" along normal blind 2 separate body makes body 194 in component "MM16 Upward-facing radiator panel"
ref_plane "WorkPlane2" through (0, 0, 998) normal (0, 0, 1) x (1, 0, 0) in component "MM16 Upward-facing radiator panel"
sketch "Shallow panel edge sketch" plane through (0, 0, 998) normal (0, 0, 1) x (1, 0, 0) in component "MM16 Upward-facing radiator panel"
  line L0 (-750, -400) -> (-748, -400)
  line L1 (-748, -400) -> (-748, 400)
  line L2 (-748, 400) -> (-750, 400)
  line L3 (-750, 400) -> (-750, -400)
extrude "Shallow panel edge" add sketch "Shallow panel edge sketch" along normal blind 20 bodies 194 in component "MM16 Upward-facing radiator panel"
ref_plane "WorkPlane3" through (0, 0, 998) normal (0, 0, 1) x (1, 0, 0) in component "MM16 Upward-facing radiator panel"
sketch "Shallow panel edge sketch (1)" plane through (0, 0, 998) normal (0, 0, 1) x (1, 0, 0) in component "MM16 Upward-facing radiator panel"
  line L0 (748, -400) -> (750, -400)
  line L1 (750, -400) -> (750, 400)
  line L2 (750, 400) -> (748, 400)
  line L3 (748, 400) -> (748, -400)
extrude "Shallow panel edge (1)" add sketch "Shallow panel edge sketch (1)" along normal blind 20 bodies 194 in component "MM16 Upward-facing radiator panel"
ref_plane "WorkPlane4" through (0, 0, 998) normal (0, 0, 1) x (1, 0, 0) in component "MM16 Upward-facing radiator panel"
sketch "Shallow panel edge sketch (2)" plane through (0, 0, 998) normal (0, 0, 1) x (1, 0, 0) in component "MM16 Upward-facing radiator panel"
  line L0 (-750, -400) -> (750, -400)
  line L1 (750, -400) -> (750, -398)
  line L2 (750, -398) -> (-750, -398)
  line L3 (-750, -398) -> (-750, -400)
extrude "Shallow panel edge (2)" add sketch "Shallow panel edge sketch (2)" along normal blind 20 bodies 194 in component "MM16 Upward-facing radiator panel"
ref_plane "WorkPlane5" through (0, 0, 998) normal (0, 0, 1) x (1, 0, 0) in component "MM16 Upward-facing radiator panel"
sketch "Shallow panel edge sketch (3)" plane through (0, 0, 998) normal (0, 0, 1) x (1, 0, 0) in component "MM16 Upward-facing radiator panel"
  line L0 (-750, 398) -> (750, 398)
  line L1 (750, 398) -> (750, 400)
  line L2 (750, 400) -> (-750, 400)
  line L3 (-750, 400) -> (-750, 398)
extrude "Shallow panel edge (3)" add sketch "Shallow panel edge sketch (3)" along normal blind 20 bodies 194 in component "MM16 Upward-facing radiator panel"
ref_plane "WorkPlane6" through (0, 0, 1004) normal (0, 0, 1) x (1, 0, 0) in component "MM16 Upward-facing radiator panel"